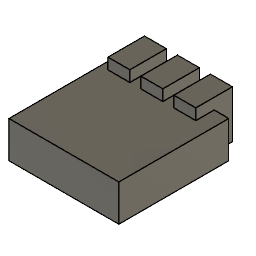
combine_tools_n3 (Autodesk Fusion 360 design; units mm, degrees)
Autodesk Fusion 360 part; units mm, degrees
sketch "Sketch1" plane through (0, 0, 0) normal (0, 0, 1) x (1, 0, 0)
  line L0 (0, 0) -> (30, 0)
  line L1 (30, 0) -> (30, 30)
  line L2 (30, 30) -> (0, 30)
  line L3 (0, 30) -> (0, 0)
extrude "Extrude1" add sketch "Sketch1" along normal blind 10 makes body 1
sketch "Sketch2" plane through (0, 0, 0) normal (0, 0, 1) x (1, 0, 0)
  line L0 (2, 25) -> (8, 25)
  line L1 (8, 25) -> (8, 35)
  line L2 (8, 35) -> (2, 35)
  line L3 (2, 35) -> (2, 25)
extrude "Extrude2" add sketch "Sketch2" along normal blind 13 separate body makes body 2
sketch "Sketch3" plane through (0, 0, 0) normal (0, 0, 1) x (1, 0, 0)
  line L0 (11, 25) -> (17, 25)
  line L1 (17, 25) -> (17, 35)
  line L2 (17, 35) -> (11, 35)
  line L3 (11, 35) -> (11, 25)
extrude "Extrude3" add sketch "Sketch3" along normal blind 13 separate body makes body 3
sketch "Sketch4" plane through (0, 0, 0) normal (0, 0, 1) x (1, 0, 0)
  line L0 (20, 25) -> (26, 25)
  line L1 (26, 25) -> (26, 35)
  line L2 (26, 35) -> (20, 35)
  line L3 (20, 35) -> (20, 25)
extrude "Extrude4" add sketch "Sketch4" along normal blind 13 separate body makes body 4
combine "Combine1" operation add target body 1 tool bodies 2 3 4
